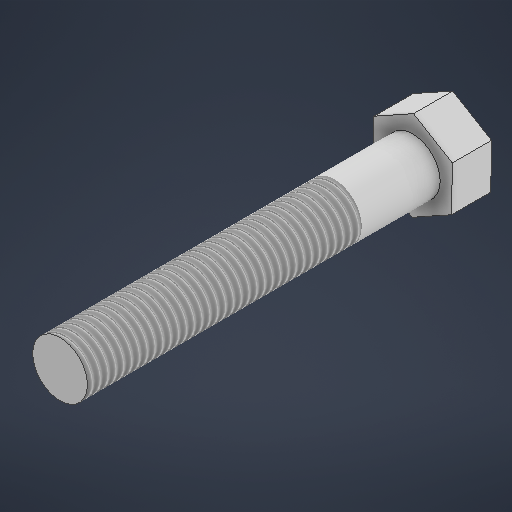
# Autodesk Inventor part: bolt
Saved by Autodesk Inventor 2025.2 (Build 292293000, 293)
## iProperties
Created: 2024-12-25
Part Number: bolt
Material: Generic
Document SubType Name: Modeling
Designer: user
Density: 1 g/cm^3
Appearance: Default
Author: user
Autodesk Inventor part; units mm, degrees
ref_plane "YZ Plane" through (0, 0, 0) normal (1, 0, 0) x (0, 1, 0)
ref_plane "XZ Plane" through (0, 0, 0) normal (0, 1, 0) x (-1, 0, 0)
ref_plane "XY Plane" through (0, 0, 0) normal (0, 0, 1) x (1, 0, 0)
sketch "Sketch1" plane through (0, 0, 0) normal (0, 0, 1) x (1, 0, 0)
  line L0 (25.7426, 19.1856) -> (15.8386, 25.1223)
  line L1 (15.8386, 25.1223) -> (16.0279, 36.6677)
  line L2 (16.0279, 36.6677) -> (26.1212, 42.2766)
  line L3 (26.1212, 42.2766) -> (36.0252, 36.3399)
  line L4 (36.0252, 36.3399) -> (35.8359, 24.7945)
  line L5 (35.8359, 24.7945) -> (25.7426, 19.1856)
  point P0 (0, 0)
  point P1 (25.9319, 30.7311)
  point P2 (30.7893, 21.9901)
  dimension "d0" = 20
  constraints: 12 end point, 1 midpoint, 13 other
  measures "d0" distance from line of point (30.789, 21.99) L2
extrude "Extrusion1" add sketch "Sketch1" along normal blind 10
sketch "Sketch2" plane through (0, 0, 10) normal (0, 0, 1) x (1, 0, 0)
  circle A0 centre (25.9319, 30.7311) radius 7
  line L0 (16.0279, 36.6677) -> (15.8386, 25.1223) projected
  line L1 (15.9332, 30.895) -> (35.9306, 30.5672)
  line L2 (35.8359, 24.7945) -> (36.0252, 36.3399) projected
  point P0 (0, 0)
  dimension "d3" = 14
  constraints: 3 midpoint, 2 coincident, 2 end point, 1 centre point
  measures "d3" diameter of A0
extrude "Extrusion2" add sketch "Sketch2" along normal blind 90
thread "Thread1" size "M14x2" class "6g" standard "ANSI Metric M Profile" length 70 offset 20
body "Solid1"
